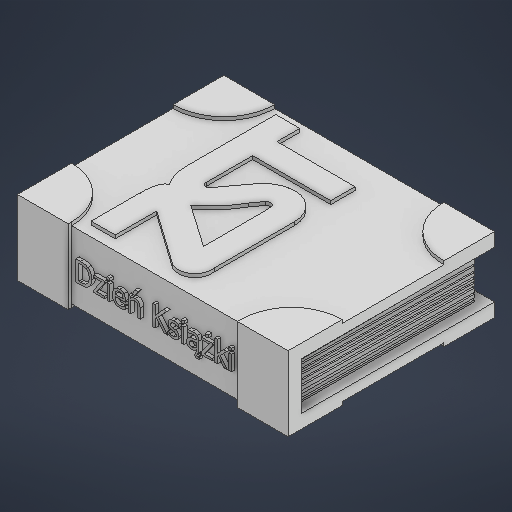
# Autodesk Inventor part: ksiazka
Saved by Autodesk Inventor 2027.1 (Build 311270010, 270A)
## iProperties
Created: 2026-10-06
Part Number: ksiazka
Material: Ogólny
Document SubType Name: Modeling
Designer: Uczeń
Density: 1 g/cm^3
Appearance: Domyślna
Author: Uczeń
Autodesk Inventor part; units mm, degrees
ref_plane "YZ Plane" through (0, 0, 0) normal (1, 0, 0) x (0, 1, 0)
ref_plane "XZ Plane" through (0, 0, 0) normal (0, 1, 0) x (-1, 0, 0)
ref_plane "XY Plane" through (0, 0, 0) normal (0, 0, 1) x (1, 0, 0)
sketch "Szkic3" plane through (0, 0, 0) normal (0, 1, 0) x (-1, 0, 0)
  line L0 (4.3087, 2.9574) -> (-3.6913, 2.9574)
  line L1 (-3.6913, 2.9574) -> (-3.6913, -3.0426)
  line L2 (-3.6913, -3.0426) -> (4.3087, -3.0426)
  line L3 (4.3087, -3.0426) -> (4.3087, 2.9574)
  point P0 (0, 0)
  dimension "d0" = 8
  dimension "d1" = 6
  constraints: 8 end point, 2 parallel, 1 horizontal, 1 perpendicular
  measures "d0" distance of L2.end L1.end
  measures "d1" distance of L1.end L0.end
extrude "Wyciągnięcie proste1" add sketch "Szkic3" along normal blind 2
sketch "Szkic4" plane through (3.6913, 0, 2.9574) normal (1, 0, 0) x (0, 0, -1)
  line L0 (0, 2) -> (6, 2) projected
  line L1 (0, 2) -> (6, 2)
  line L2 (6, 2) -> (6, 0)
  line L3 (6, 0) -> (0, 0)
  line L4 (0, 0) -> (0, 2)
  line L5 (6, 0) -> (6, 0.3)
  line L6 (6, 0.3) -> (0, 0.3)
  line L7 (6, 2) -> (6, 1.7)
  line L8 (6, 1.7) -> (0, 1.7)
  line L9 (0, 1.7) -> (0.3, 1.7)
  line L10 (0.3, 1.7) -> (0.3, 0.3)
  point P0 (2.9574, 0)
  dimension "d4" = 0.3
  dimension "d5" = 0.3
  dimension "d6" = 0.3
  constraints: 20 end point, 6 point on line, 4 perpendicular, 2 parallel, 1 horizontal
  measures "d4" distance of L2.end L5.end
  measures "d5" distance of L1.end L7.end
  measures "d6" distance of L8.end L9.end
extrude "Wyciągnięcie proste2" cut sketch "Szkic4" against normal blind 0.3 contours L2 L6 L10 L8
sketch "Szkic5" plane through (-4.3087, 0, -3.0426) normal (-1, 0, 0) x (0, 0, 1)
  line L0 (6, 2) -> (0, 2) projected
  line L1 (0, 2) -> (0, 1.7)
  line L2 (0, 0) -> (0, 2) projected
  line L3 (0, 1.7) -> (6, 1.7)
  line L4 (6, 0) -> (6, 2) projected
  line L5 (6, 0) -> (0, 0) projected
  line L6 (0, 0) -> (0, 0.3)
  line L7 (0, 0.3) -> (6, 0.3)
  line L8 (5.7, 0.3) -> (5.7, 1.7) projected
  line L9 (5.7, 1.7) -> (5.7, 0.3)
  point P0 (3.0426, 0)
  dimension "d9" = 0.3
  dimension "d10" = 0.3
  constraints: 10 end point, 4 point on line, 2 perpendicular, 1 collinear
  measures "d9" distance of L0.end L1.end
  measures "d10" distance of L2.start L6.end
extrude "Wyciągnięcie proste3" cut sketch "Szkic5" against normal blind 0.3 contours L3 L8 L7 L2
sketch "Szkic6" plane through (3.6913, 0, -3.0426) normal (0, 0, -1) x (-1, 0, 0)
  line L0 (0.3, 1.7) -> (0.3, 0.3) projected
  line L1 (8, 0.3) -> (7.7, 0.3) projected
  line L2 (0.3, 0.3) -> (7.7, 0.3)
  line L3 (7.7, 0.3) -> (7.7, 1.7) projected
  line L4 (7.7, 0.3) -> (7.7, 1.7)
  line L5 (7.7, 1.7) -> (0.3, 1.7)
  line L6 (0.3, 1.7) -> (0.3, 0.3)
  point P0 (3.6913, 0)
  constraints: 8 end point, 3 perpendicular, 1 horizontal
extrude "Wyciągnięcie proste4" cut sketch "Szkic6" against normal blind 0.3
sketch "Szkic7" plane through (0, 2, 0) normal (0, 1, 0) x (1, 0, 0)
  line L0 (-4.3087, 3.0426) -> (3.6913, 3.0426) projected
  line L1 (-4.3087, -2.6574) -> (-4.3087, 3.0426) projected
  circle A0 centre (-4.3087, 3.0426) radius 1.5
  circle A1 centre (3.6913, 3.0426) radius 1.5
  line L2 (3.6913, 3.0426) -> (3.6913, -2.6574) projected
  line L3 (3.6913, 3.0426) -> (3.6913, 1.5426)
  line L4 (3.6913, 3.0426) -> (2.1913, 3.0426)
  line L5 (3.6913, -2.9574) -> (3.6913, 3.0426) projected
  circle A2 centre (3.6913, -2.9574) radius 1.5
  circle A3 centre (-4.3087, -2.9574) radius 1.5
  line L6 (-4.3087, -2.9574) -> (-4.3087, -1.4574)
  line L7 (-4.3087, -2.9574) -> (3.6913, -2.9574) projected
  line L8 (-4.3087, -2.9574) -> (-2.8087, -2.9574)
  line L9 (2.1913, -2.9574) -> (3.6913, -2.9574)
  line L10 (3.6913, -1.4574) -> (3.6913, -2.9574)
  point P0 (0, 0)
  point P1 (-4.3087, 1.5426)
  point P2 (-2.8087, 3.0426)
  point P3 (2.1913, -2.9574)
  point P4 (3.6913, -1.4574)
  dimension "d16" = 3
  dimension "d17" = 3
  dimension "d18" = 3
  dimension "d19" = 3
  constraints: 12 end point, 6 point on circle, 6 point on line, 4 centre point, 2 coincident, 2 collinear
  measures "d16" diameter of A0
  measures "d17" diameter of A1
  measures "d18" diameter of A2
  measures "d19" diameter of A3
extrude "Wyciągnięcie proste5" add sketch "Szkic7" along normal blind 0.1 contours L0 A0 L1 | L0 L2 A1 | A3 L7 L6 L1 | L2 L5 L7 A2 picked at (-3.78, 2.2012) picked at (3.58, 2.0551) picked at (-3.3212, -2.8461) picked at (2.7038, -2.8461)
sketch "Szkic8" plane through (0, 0, 0) normal (0, -1, 0) x (1, 0, 0)
  line L0 (3.6913, -3.0426) -> (-4.3087, -3.0426) projected
  circle A0 centre (-4.3087, -3.0426) radius 1.5
  line L1 (-4.3087, 1.4574) -> (-4.3087, 2.9574) projected
  circle A1 centre (-4.3087, 2.9574) radius 1.5
  line L2 (-4.3087, 2.9574) -> (3.6913, 2.9574) projected
  circle A2 centre (3.6913, 2.9574) radius 1.5
  line L3 (3.6913, 2.9574) -> (3.6913, -3.0426) projected
  circle A3 centre (3.6913, -3.0426) radius 1.5
  line L4 (-4.3087, -3.0426) -> (-4.3087, 2.9574) projected
  line L5 (-4.3087, -1.5426) -> (-4.3087, -3.0426)
  line L6 (-4.3087, -3.0426) -> (-2.8087, -3.0426)
  line L7 (2.1913, -3.0426) -> (3.6913, -3.0426)
  line L8 (3.6913, -1.5426) -> (3.6913, -3.0426)
  line L9 (3.6913, 1.4574) -> (3.6913, 2.9574)
  line L10 (3.6913, 2.9574) -> (2.1913, 2.9574)
  point P0 (0, 0)
  point P1 (-4.3087, -3.0279)
  point P2 (-2.8087, 2.9574)
  dimension "d26" = 3
  dimension "d27" = 3
  dimension "d28" = 3
  dimension "d29" = 3
  constraints: 12 end point, 6 point on circle, 6 point on line, 4 centre point, 3 collinear, 1 coincident, 1 perpendicular
  measures "d26" diameter of A0
  measures "d27" diameter of A1
  measures "d28" diameter of A2
  measures "d29" diameter of A3
extrude "Wyciągnięcie proste6" add sketch "Szkic8" along normal blind 0.1 contours L0 A3 L3 | L0 L4 A0 | A2 L2 L3 | L1 L2 A1 picked at (2.7534, -2.7144) picked at (-3.78, -2.2012) picked at (3.58, 1.9699) picked at (-3.3212, 2.8461)
sketch "Szkic9" plane through (-2.8087, 2, 2.9574) normal (0, 0, 1) x (1, 0, 0)
  line L0 (-1.5, 0.1) -> (0, 0.1) projected
  line L1 (0, -2.1) -> (-1.5, -2.1) projected
  line L2 (0, 0.1) -> (0, -2.1)
  line L3 (5, 0.1) -> (6.5, 0.1) projected
  line L4 (5, -2.1) -> (6.5, -2.1) projected
  line L5 (5, 0.1) -> (5, -2.1)
  line L6 (0.168, -0.6066) -> (4.8954, -0.6066) construction
  line L7 (4.8954, -0.6066) -> (4.8954, -1.5064) construction
  line L8 (4.8954, -1.5064) -> (0.168, -1.5064) construction
  line L9 (0.168, -1.5064) -> (0.168, -0.6066) construction
  line L10 (-1.5, -2.1) -> (-1.5, 0.1) projected
  line L11 (-1.5, -2.1) -> (-1.5, 0.1)
  line L12 (6.5, 0.1) -> (6.5, -2.1)
  spline S0 degree 2 poles (0.7019, -0.9825) (0.7019, -1.0646) (0.6353, -1.1969) (0.5794, -1.2339) knots 0 0 0 1 2 2 2
  spline S1 degree 2 poles (0.5794, -1.2339) (0.5337, -1.2625) (0.4398, -1.282) (0.3669, -1.282) knots 0 0 0 1 2 2 2
  line L13 (0.3669, -1.282) -> (0.2288, -1.282)
  line L14 (0.2288, -1.282) -> (0.2288, -0.682)
  line L15 (0.2288, -0.682) -> (0.3654, -0.682)
  spline S2 degree 2 poles (0.3654, -0.682) (0.45, -0.682) (0.5463, -0.7073) (0.5803, -0.7296) knots 0 0 0 1 2 2 2
  spline S3 degree 2 poles (0.5803, -0.7296) (0.6382, -0.7681) (0.7019, -0.895) (0.7019, -0.9825) knots 0 0 0 1 2 2 2
  spline S4 degree 2 poles (0.6188, -0.9815) (0.6188, -0.9125) (0.5731, -0.8147) (0.5278, -0.787) knots 0 0 0 1 2 2 2
  spline S5 degree 2 poles (0.5278, -0.787) (0.4957, -0.7681) (0.4233, -0.751) (0.3693, -0.751) knots 0 0 0 1 2 2 2
  line L16 (0.3693, -0.751) -> (0.3085, -0.751)
  line L17 (0.3085, -0.751) -> (0.3085, -1.2129)
  line L18 (0.3085, -1.2129) -> (0.3693, -1.2129)
  spline S6 degree 2 poles (0.3693, -1.2129) (0.4223, -1.2129) (0.5026, -1.1959) (0.5351, -1.1731) knots 0 0 0 1 2 2 2
  spline S7 degree 2 poles (0.5351, -1.1731) (0.5769, -1.1449) (0.6188, -1.0515) (0.6188, -0.9815) knots 0 0 0 1 2 2 2
  line L19 (1.0782, -1.282) -> (0.7476, -1.282)
  line L20 (0.7476, -1.282) -> (0.7476, -1.2256)
  line L21 (0.7476, -1.2256) -> (0.9829, -0.894)
  line L22 (0.9829, -0.894) -> (0.7573, -0.894)
  line L23 (0.7573, -0.894) -> (0.7573, -0.8317)
  line L24 (0.7573, -0.8317) -> (1.0739, -0.8317)
  line L25 (1.0739, -0.8317) -> (1.0739, -0.8857)
  line L26 (1.0739, -0.8857) -> (0.8376, -1.2183)
  line L27 (0.8376, -1.2183) -> (1.0782, -1.2183)
  line L28 (1.0782, -1.2183) -> (1.0782, -1.282)
  line L29 (1.2265, -1.282) -> (1.1507, -1.282)
  line L30 (1.1507, -1.282) -> (1.1507, -0.8317)
  line L31 (1.1507, -0.8317) -> (1.2265, -0.8317)
  line L32 (1.2265, -0.8317) -> (1.2265, -1.282)
  line L33 (1.2319, -0.7569) -> (1.1458, -0.7569)
  line L34 (1.1458, -0.7569) -> (1.1458, -0.6781)
  line L35 (1.1458, -0.6781) -> (1.2319, -0.6781)
  line L36 (1.2319, -0.6781) -> (1.2319, -0.7569)
  spline S8 degree 2 poles (1.5333, -1.2922) (1.4254, -1.2922) (1.3068, -1.1711) (1.3068, -1.0593) knots 0 0 0 1 2 2 2
  spline S9 degree 2 poles (1.3068, -1.0593) (1.3068, -0.9494) (1.422, -0.8191) (1.5149, -0.8191) knots 0 0 0 1 2 2 2
  spline S10 degree 2 poles (1.5149, -0.8191) (1.5567, -0.8191) (1.6214, -0.8434) (1.6452, -0.8692) knots 0 0 0 1 2 2 2
  spline S11 degree 2 poles (1.6452, -0.8692) (1.6695, -0.895) (1.6953, -0.9693) (1.6953, -1.0233) knots 0 0 0 1 2 2 2
  line L37 (1.6953, -1.0233) -> (1.6953, -1.0646)
  line L38 (1.6953, -1.0646) -> (1.3836, -1.0646)
  spline S12 degree 2 poles (1.3836, -1.0646) (1.3836, -1.1429) (1.4624, -1.2261) (1.5324, -1.2261) knots 0 0 0 1 2 2 2
  spline S13 degree 2 poles (1.5324, -1.2261) (1.5572, -1.2261) (1.6053, -1.2149) (1.6248, -1.2061) knots 0 0 0 1 2 2 2
  spline S14 degree 2 poles (1.6248, -1.2061) (1.6452, -1.1964) (1.6734, -1.1794) (1.6826, -1.1716) knots 0 0 0 1 2 2 2
  line L39 (1.6826, -1.1716) -> (1.687, -1.1716)
  line L40 (1.687, -1.1716) -> (1.687, -1.2543)
  spline S15 degree 2 poles (1.687, -1.2543) (1.6739, -1.2596) (1.634, -1.2752) (1.6184, -1.2796) knots 0 0 0 1 2 2 2
  spline S16 degree 2 poles (1.6184, -1.2796) (1.5966, -1.2859) (1.5606, -1.2922) (1.5333, -1.2922) knots 0 0 0 1 2 2 2
  spline S17 degree 2 poles (1.6214, -1.0068) (1.6204, -0.9762) (1.6077, -0.9314) (1.5956, -0.9163) knots 0 0 0 1 2 2 2
  spline S18 degree 2 poles (1.5956, -0.9163) (1.5825, -0.8993) (1.5411, -0.8813) (1.5105, -0.8813) knots 0 0 0 1 2 2 2
  spline S19 degree 2 poles (1.5105, -0.8813) (1.4803, -0.8813) (1.438, -0.8993) (1.4205, -0.9168) knots 0 0 0 1 2 2 2
  spline S20 degree 2 poles (1.4205, -0.9168) (1.4035, -0.9348) (1.386, -0.9781) (1.3836, -1.0068) knots 0 0 0 1 2 2 2
  line L41 (1.3836, -1.0068) -> (1.6214, -1.0068)
  line L42 (2.1256, -1.282) -> (2.0497, -1.282)
  line L43 (2.0497, -1.282) -> (2.0497, -1.0253)
  spline S21 degree 2 poles (2.0497, -1.0253) (2.0497, -0.9941) (2.0439, -0.9407) (2.0351, -0.9246) knots 0 0 0 1 2 2 2
  spline S22 degree 2 poles (2.0351, -0.9246) (2.0259, -0.9076) (1.9928, -0.8911) (1.9646, -0.8911) knots 0 0 0 1 2 2 2
  spline S23 degree 2 poles (1.9646, -0.8911) (1.9364, -0.8911) (1.8766, -0.9212) (1.8479, -0.9455) knots 0 0 0 1 2 2 2
  line L44 (1.8479, -0.9455) -> (1.8479, -1.282)
  line L45 (1.8479, -1.282) -> (1.7721, -1.282)
  line L46 (1.7721, -1.282) -> (1.7721, -0.8317)
  line L47 (1.7721, -0.8317) -> (1.8479, -0.8317)
  line L48 (1.8479, -0.8317) -> (1.8479, -0.8818)
  spline S24 degree 2 poles (1.8479, -0.8818) (1.882, -0.8512) (1.9476, -0.8191) (1.9846, -0.8191) knots 0 0 0 1 2 2 2
  spline S25 degree 2 poles (1.9846, -0.8191) (2.0507, -0.8191) (2.1256, -0.9066) (2.1256, -0.9898) knots 0 0 0 1 2 2 2
  line L49 (2.1256, -0.9898) -> (2.1256, -1.282)
  line L50 (2.0677, -0.6066) -> (1.9578, -0.7574)
  line L51 (1.9578, -0.7574) -> (1.8975, -0.7574)
  line L52 (1.8975, -0.7574) -> (1.9695, -0.6066)
  line L53 (1.9695, -0.6066) -> (2.0677, -0.6066)
  line L54 (2.9332, -1.282) -> (2.8296, -1.282)
  line L55 (2.8296, -1.282) -> (2.6103, -1.0029)
  line L56 (2.6103, -1.0029) -> (2.5753, -1.0423)
  line L57 (2.5753, -1.0423) -> (2.5753, -1.282)
  line L58 (2.5753, -1.282) -> (2.4956, -1.282)
  line L59 (2.4956, -1.282) -> (2.4956, -0.682)
  line L60 (2.4956, -0.682) -> (2.5753, -0.682)
  line L61 (2.5753, -0.682) -> (2.5753, -0.9577)
  line L62 (2.5753, -0.9577) -> (2.8214, -0.682)
  line L63 (2.8214, -0.682) -> (2.9186, -0.682)
  line L64 (2.9186, -0.682) -> (2.6701, -0.9499)
  line L65 (2.6701, -0.9499) -> (2.9332, -1.282)
  spline S26 degree 2 poles (3.0966, -1.2927) (3.0513, -1.2927) (2.9731, -1.2684) (2.9473, -1.2548) knots 0 0 0 1 2 2 2
  line L66 (2.9473, -1.2548) -> (2.9473, -1.1697)
  line L67 (2.9473, -1.1697) -> (2.9512, -1.1697)
  spline S27 degree 2 poles (2.9512, -1.1697) (2.9609, -1.1775) (2.9872, -1.1959) (3.009, -1.2061) knots 0 0 0 1 2 2 2
  spline S28 degree 2 poles (3.009, -1.2061) (3.028, -1.2154) (3.0747, -1.229) (3.0995, -1.229) knots 0 0 0 1 2 2 2
  spline S29 degree 2 poles (3.0995, -1.229) (3.1175, -1.229) (3.1588, -1.2207) (3.1685, -1.2139) knots 0 0 0 1 2 2 2
  spline S30 degree 2 poles (3.1685, -1.2139) (3.1826, -1.2047) (3.1953, -1.1838) (3.1953, -1.1624) knots 0 0 0 1 2 2 2
  spline S31 degree 2 poles (3.1953, -1.1624) (3.1953, -1.1356) (3.1661, -1.1079) (3.1286, -1.0987) knots 0 0 0 1 2 2 2
  spline S32 degree 2 poles (3.1286, -1.0987) (3.1141, -1.0953) (3.0674, -1.0856) (3.0474, -1.0802) knots 0 0 0 1 2 2 2
  spline S33 degree 2 poles (3.0474, -1.0802) (2.9959, -1.0651) (2.9492, -1.0029) (2.9492, -0.9587) knots 0 0 0 1 2 2 2
  spline S34 degree 2 poles (2.9492, -0.9587) (2.9492, -0.8974) (3.0411, -0.8211) (3.117, -0.8211) knots 0 0 0 1 2 2 2
  spline S35 degree 2 poles (3.117, -0.8211) (3.1544, -0.8211) (3.2303, -0.8395) (3.256, -0.8536) knots 0 0 0 1 2 2 2
  line L68 (3.256, -0.8536) -> (3.256, -0.9348)
  line L69 (3.256, -0.9348) -> (3.2521, -0.9348)
  spline S36 degree 2 poles (3.2521, -0.9348) (3.223, -0.9115) (3.152, -0.8847) (3.1155, -0.8847) knots 0 0 0 1 2 2 2
  spline S37 degree 2 poles (3.1155, -0.8847) (3.0781, -0.8847) (3.0265, -0.9163) (3.0265, -0.948) knots 0 0 0 1 2 2 2
  spline S38 degree 2 poles (3.0265, -0.948) (3.0265, -0.9766) (3.0572, -1.0044) (3.0912, -1.0131) knots 0 0 0 1 2 2 2
  spline S39 degree 2 poles (3.0912, -1.0131) (3.1077, -1.0175) (3.1496, -1.0262) (3.1724, -1.0316) knots 0 0 0 1 2 2 2
  spline S40 degree 2 poles (3.1724, -1.0316) (3.222, -1.0442) (3.2726, -1.1021) (3.2726, -1.1522) knots 0 0 0 1 2 2 2
  spline S41 degree 2 poles (3.2726, -1.1522) (3.2726, -1.1813) (3.2497, -1.2329) (3.2273, -1.2518) knots 0 0 0 1 2 2 2
  spline S42 degree 2 poles (3.2273, -1.2518) (3.2035, -1.2718) (3.1427, -1.2927) (3.0966, -1.2927) knots 0 0 0 1 2 2 2
  line L70 (3.4204, -1.282) -> (3.3445, -1.282)
  line L71 (3.3445, -1.282) -> (3.3445, -0.8317)
  line L72 (3.3445, -0.8317) -> (3.4204, -0.8317)
  line L73 (3.4204, -0.8317) -> (3.4204, -1.282)
  line L74 (3.4257, -0.7569) -> (3.3397, -0.7569)
  line L75 (3.3397, -0.7569) -> (3.3397, -0.6781)
  line L76 (3.3397, -0.6781) -> (3.4257, -0.6781)
  line L77 (3.4257, -0.6781) -> (3.4257, -0.7569)
  spline S43 degree 2 poles (3.7826, -1.2343) (3.7734, -1.2411) (3.7423, -1.2655) (3.7277, -1.2728) knots 0 0 0 1 2 2 2
  spline S44 degree 2 poles (3.7277, -1.2728) (3.7077, -1.2834) (3.6703, -1.2946) (3.6363, -1.2946) knots 0 0 0 1 2 2 2
  spline S45 degree 2 poles (3.6363, -1.2946) (3.6085, -1.2946) (3.5585, -1.2737) (3.5395, -1.2548) knots 0 0 0 1 2 2 2
  spline S46 degree 2 poles (3.5395, -1.2548) (3.5215, -1.2363) (3.4996, -1.1818) (3.4996, -1.1517) knots 0 0 0 1 2 2 2
  spline S47 degree 2 poles (3.4996, -1.1517) (3.4996, -1.105) (3.539, -1.0389) (3.5818, -1.0199) knots 0 0 0 1 2 2 2
  spline S48 degree 2 poles (3.5818, -1.0199) (3.6197, -1.0024) (3.7228, -0.9893) (3.7826, -0.9859) knots 0 0 0 1 2 2 2
  line L78 (3.7826, -0.9859) -> (3.7826, -0.9713)
  spline S49 degree 2 poles (3.7826, -0.9713) (3.7826, -0.945) (3.7666, -0.9125) (3.752, -0.9032) knots 0 0 0 1 2 2 2
  spline S50 degree 2 poles (3.752, -0.9032) (3.7374, -0.894) (3.6956, -0.8881) (3.6732, -0.8881) knots 0 0 0 1 2 2 2
  spline S51 degree 2 poles (3.6732, -0.8881) (3.647, -0.8881) (3.576, -0.9037) (3.5405, -0.9188) knots 0 0 0 1 2 2 2
  line L79 (3.5405, -0.9188) -> (3.5361, -0.9188)
  line L80 (3.5361, -0.9188) -> (3.5361, -0.8415)
  spline S52 degree 2 poles (3.5361, -0.8415) (3.557, -0.8356) (3.6353, -0.8211) (3.6737, -0.8211) knots 0 0 0 1 2 2 2
  spline S53 degree 2 poles (3.6737, -0.8211) (3.7204, -0.8211) (3.7841, -0.8356) (3.8094, -0.8546) knots 0 0 0 1 2 2 2
  spline S54 degree 2 poles (3.8094, -0.8546) (3.8342, -0.8731) (3.8585, -0.9319) (3.8585, -0.9742) knots 0 0 0 1 2 2 2
  line L81 (3.8585, -0.9742) -> (3.8585, -1.282)
  line L82 (3.8585, -1.282) -> (3.7826, -1.282)
  line L83 (3.7826, -1.282) -> (3.7826, -1.2343)
  line L84 (3.7826, -1.1711) -> (3.7826, -1.0462)
  spline S55 degree 2 poles (3.7826, -1.0462) (3.7554, -1.0486) (3.6732, -1.0569) (3.6474, -1.0646) knots 0 0 0 1 2 2 2
  spline S56 degree 2 poles (3.6474, -1.0646) (3.6173, -1.0739) (3.5779, -1.1123) (3.5779, -1.1463) knots 0 0 0 1 2 2 2
  spline S57 degree 2 poles (3.5779, -1.1463) (3.5779, -1.1852) (3.6217, -1.2246) (3.6635, -1.2246) knots 0 0 0 1 2 2 2
  spline S58 degree 2 poles (3.6635, -1.2246) (3.699, -1.2246) (3.7573, -1.194) (3.7826, -1.1711) knots 0 0 0 1 2 2 2
  spline S59 degree 2 poles (3.8487, -1.282) (3.8312, -1.2966) (3.805, -1.3399) (3.805, -1.3588) knots 0 0 0 1 2 2 2
  spline S60 degree 2 poles (3.805, -1.3588) (3.805, -1.3719) (3.8201, -1.3885) (3.8351, -1.3885) knots 0 0 0 1 2 2 2
  spline S61 degree 2 poles (3.8351, -1.3885) (3.8434, -1.3885) (3.8585, -1.3846) (3.8633, -1.3826) knots 0 0 0 1 2 2 2
  line L85 (3.8633, -1.3826) -> (3.8677, -1.3826)
  line L86 (3.8677, -1.3826) -> (3.8677, -1.439)
  spline S62 degree 2 poles (3.8677, -1.439) (3.856, -1.4439) (3.8303, -1.4483) (3.8196, -1.4483) knots 0 0 0 1 2 2 2
  spline S63 degree 2 poles (3.8196, -1.4483) (3.7836, -1.4483) (3.7427, -1.4108) (3.7427, -1.3773) knots 0 0 0 1 2 2 2
  spline S64 degree 2 poles (3.7427, -1.3773) (3.7427, -1.351) (3.7709, -1.299) (3.7889, -1.282) knots 0 0 0 1 2 2 2
  line L87 (3.7889, -1.282) -> (3.8487, -1.282)
  line L88 (4.2606, -1.282) -> (3.9299, -1.282)
  line L89 (3.9299, -1.282) -> (3.9299, -1.2256)
  line L90 (3.9299, -1.2256) -> (4.1653, -0.894)
  line L91 (4.1653, -0.894) -> (3.9397, -0.894)
  line L92 (3.9397, -0.894) -> (3.9397, -0.8317)
  line L93 (3.9397, -0.8317) -> (4.2562, -0.8317)
  line L94 (4.2562, -0.8317) -> (4.2562, -0.8857)
  line L95 (4.2562, -0.8857) -> (4.0199, -1.2183)
  line L96 (4.0199, -1.2183) -> (4.2606, -1.2183)
  line L97 (4.2606, -1.2183) -> (4.2606, -1.282)
  line L98 (4.1346, -0.7564) -> (4.0486, -0.7564)
  line L99 (4.0486, -0.7564) -> (4.0486, -0.6776)
  line L100 (4.0486, -0.6776) -> (4.1346, -0.6776)
  line L101 (4.1346, -0.6776) -> (4.1346, -0.7564)
  line L102 (4.7045, -1.282) -> (4.6048, -1.282)
  line L103 (4.6048, -1.282) -> (4.4376, -1.0646)
  line L104 (4.4376, -1.0646) -> (4.4074, -1.0938)
  line L105 (4.4074, -1.0938) -> (4.4074, -1.282)
  line L106 (4.4074, -1.282) -> (4.3316, -1.282)
  line L107 (4.3316, -1.282) -> (4.3316, -0.6552)
  line L108 (4.3316, -0.6552) -> (4.4074, -0.6552)
  line L109 (4.4074, -0.6552) -> (4.4074, -1.0219)
  line L110 (4.4074, -1.0219) -> (4.5854, -0.8317)
  line L111 (4.5854, -0.8317) -> (4.6797, -0.8317)
  line L112 (4.6797, -0.8317) -> (4.4949, -1.0199)
  line L113 (4.4949, -1.0199) -> (4.7045, -1.282)
  line L114 (4.8197, -1.282) -> (4.7439, -1.282)
  line L115 (4.7439, -1.282) -> (4.7439, -0.8317)
  line L116 (4.7439, -0.8317) -> (4.8197, -0.8317)
  line L117 (4.8197, -0.8317) -> (4.8197, -1.282)
  line L118 (4.8251, -0.7569) -> (4.739, -0.7569)
  line L119 (4.739, -0.7569) -> (4.739, -0.6781)
  line L120 (4.739, -0.6781) -> (4.8251, -0.6781)
  line L121 (4.8251, -0.6781) -> (4.8251, -0.7569)
  point P0 (2.8087, -2)
  constraints: 8 end point, 2 vertical, 1 collinear, 1 perpendicular, 2 other
extrude "Wyciągnięcie proste7" add sketch "Szkic9" along normal blind 0.1
sketch "Szkic10" plane through (0, 2, 0) normal (0, 1, 0) x (1, 0, 0)
  line L0 (-2.5369, -2.6492) -> (-1.8273, -2.6492)
  line L1 (-1.8273, -2.6492) -> (-1.8273, -1.4232)
  line L2 (-0.2303, -1.6373) -> (-0.2303, 0.1352)
  line L3 (-1.8273, -1.4232) -> (-0.2303, -2.5494)
  line L4 (0.481, -2.0362) -> (0.481, 0.3517)
  arc A0 (-0.2303, -2.5494) -> (0.481, -2.0362) centre (-0.0008, -2.1179) ccw
  line L5 (-1.4779, -0.7683) -> (-0.2303, -1.6373)
  arc A1 (-1.4779, -0.7683) -> (-0.6777, 0.1352) centre (-3.1229, 1.4948) ccw
  arc A2 (-0.4511, 0.422) -> (-0.6777, 0.1352) centre (0.8334, -0.8257) ccw
  arc A3 (-0.2487, 0.3742) -> (-0.4511, 0.422) centre (-0.3566, 0.3699) ccw
  arc A4 (-0.2303, 0.1352) -> (-0.2487, 0.3742) centre (-1.2429, 0.1774) ccw
  arc A5 (0.481, 0.3517) -> (-0.4687, 1.1215) centre (-0.3058, 0.3517) ccw
  arc A6 (-0.4687, 1.1215) -> (-1.0286, 0.7827) centre (-0.2631, 0.1495) ccw
  line L6 (-1.0286, 0.7827) -> (-1.6248, -0.0201)
  line L7 (-1.8273, 1.4122) -> (-1.8273, 0.0497)
  arc A7 (-1.8273, 0.0497) -> (-1.6248, -0.0201) centre (-1.7212, 0.0288) ccw
  line L8 (-1.8273, 1.4122) -> (0.481, 1.4122)
  line L9 (0.481, 1.4122) -> (0.481, 2.1298)
  line L10 (0.481, 2.1298) -> (-1.8273, 2.1298)
  line L11 (-1.8273, 2.1298) -> (-1.8273, 2.805)
  line L12 (-1.8273, 2.805) -> (-2.5369, 2.805)
  line L13 (-2.5369, 2.805) -> (-2.5369, 0.1495)
  arc A8 (-2.5369, 0.1495) -> (-2.3243, -0.5581) centre (-1.2532, 0.1495) ccw
  line L14 (-2.5369, -2.6492) -> (-2.5369, -1.2028)
  arc A9 (-2.4826, -0.7511) -> (-2.5369, -1.2028) centre (-0.6308, -1.2028) ccw
  arc A10 (-2.3243, -0.5581) -> (-2.4826, -0.7511) centre (-2.2025, -0.8194) ccw
  point P0 (0, 0)
  dimension "d104" = 1
  constraints: 30 end point, 22 point on circle, 11 centre point, 5 perpendicular, 5 tangent, 4 vertical, 3 horizontal
  measures "d104" distance of L6.start L6.end
extrude "Wyciągnięcie proste8" add sketch "Szkic10" along normal blind 0.1
sketch "Szkic11" plane through (3.3913, 0, 2.9574) normal (1, 0, 0) x (0, 0, -1)
  line L0 (5.7, 1.7) -> (5.7, 0.3) projected
  line L1 (0.3, 1.7) -> (5.7, 1.7) projected
  line L2 (5.7, 1.7) -> (0.3, 1.7)
  line L3 (0.3, 0.3) -> (0.3, 1.7) projected
  line L4 (0.3, 1.7) -> (0.3, 0.3)
  line L5 (5.7, 0.3) -> (0.3, 0.3) projected
  line L6 (0.3, 0.3) -> (5.7, 0.3)
  line L7 (5.7, 0.3) -> (5.7, 1.7)
  line L8 (5.7, 1.616) -> (0.3, 1.616)
  line L9 (0.3, 1.5656) -> (5.7, 1.5263)
  line L10 (5.7, 1.4477) -> (0.3, 1.4241)
  line L11 (0.3, 1.3848) -> (5.7, 1.4084)
  line L12 (0.3, 1.3101) -> (5.7, 1.2708)
  line L13 (5.7, 1.2197) -> (0.3, 1.259)
  line L14 (0.3, 1.1608) -> (5.7, 1.0941)
  line L15 (5.7, 1.0508) -> (0.3, 1.1175)
  line L16 (0.3, 1.0507) -> (5.7, 0.9525)
  line L17 (5.7, 0.8935) -> (0.3, 1)
  line L18 (0.3, 0.8935) -> (5.7, 0.8268)
  line L19 (5.7, 0.7835) -> (0.3, 0.8502)
  line L20 (0.3, 0.7482) -> (5.7, 0.7088)
  line L21 (5.7, 0.6538) -> (0.3, 0.6931)
  line L22 (0.3, 0.5831) -> (5.7, 0.5437)
  line L23 (5.7, 0.4966) -> (0.3, 0.4966)
  line L24 (0.3, 0.4062) -> (5.7, 0.4062)
  line L25 (5.7, 0.3512) -> (0.3, 0.3512)
  point P0 (2.9574, 0)
  point P1 (0.3, 0.4062)
  point P2 (0.3, 0.5831)
  point P3 (0.3, 0.7482)
  point P4 (0.3, 1.1608)
  point P5 (0.3, 1.3101)
  point P6 (0.3, 1.3848)
  point P7 (0.3, 1.4241)
  constraints: 40 end point, 11 equal length, 5 horizontal, 44 other
extrude "Wyciągnięcie proste9" cut sketch "Szkic11" against normal blind 0.1 contours L0 L9 L3 L8 | L0 L11 L3 L10 | L0 L13 L3 L12 | L0 L15 L3 L14 | L0 L17 L3 L16 | L0 L19 L3 L18 | L0 L21 L3 L20 | L0 L23 L3 L22 | L0 L25 L3 L24
sketch "Szkic14" plane through (-4.0087, 0, -3.0426) normal (-1, 0, 0) x (0, 0, 1)
  line L0 (0.3, 1.616) -> (0.3, 1.7) projected
  line L1 (0.3, 1.7) -> (0.3, 0.3)
  line L2 (0.3, 0.3512) -> (5.7, 0.3512) projected
  line L3 (5.7, 1.7) -> (5.7, 0.3) projected
  line L4 (0.3, 0.3) -> (5.7, 0.3)
  line L5 (5.7, 0.3) -> (5.7, 1.7)
  line L6 (5.7, 1.7) -> (0.3, 1.7)
  line L7 (5.7, 1.616) -> (0.3, 1.616) projected
  line L8 (0.3, 1.616) -> (5.7, 1.616)
  line L9 (0.3, 1.5263) -> (5.7, 1.5656) projected
  line L10 (0.3, 1.5263) -> (5.7, 1.5656)
  line L11 (5.7, 1.4241) -> (0.3, 1.4477) projected
  line L12 (0.3, 1.4477) -> (5.7, 1.4241)
  line L13 (0.3, 1.4084) -> (5.7, 1.3848) projected
  line L14 (5.7, 1.4241) -> (5.7, 1.3848)
  line L15 (5.7, 1.3848) -> (0.3, 1.4084)
  line L16 (0.3, 1.2197) -> (5.7, 1.259) projected
  line L17 (0.3, 1.2197) -> (5.7, 1.259)
  line L18 (5.7, 1.3101) -> (0.3, 1.2708) projected
  line L19 (5.7, 1.259) -> (5.7, 1.3101)
  line L20 (5.7, 1.3101) -> (0.3, 1.2708)
  line L21 (5.7, 1.1608) -> (0.3, 1.0941) projected
  line L22 (0.3, 1.2708) -> (0.3, 1.2197)
  line L23 (0.3, 0.4062) -> (0.3, 0.3512) projected
  line L24 (0.3, 0.3512) -> (0.3, 0.4062)
  line L25 (5.7, 0.4062) -> (0.3, 0.4062) projected
  line L26 (0.3, 0.4062) -> (5.7, 0.4062)
  line L27 (5.7, 0.4062) -> (5.7, 0.3512)
  line L28 (0.3, 0.4966) -> (5.7, 0.4966) projected
  line L29 (5.7, 0.4966) -> (0.3, 0.4966)
  line L30 (5.7, 0.5831) -> (0.3, 0.5437) projected
  line L31 (0.3, 0.5437) -> (5.7, 0.5831)
  line L32 (5.7, 0.5831) -> (5.7, 0.4966)
  line L33 (0.3, 0.6538) -> (5.7, 0.6931) projected
  line L34 (5.7, 0.6931) -> (0.3, 0.6538)
  line L35 (5.7, 0.7482) -> (0.3, 0.7088) projected
  line L36 (0.3, 0.6538) -> (0.3, 0.7088)
  line L37 (0.3, 0.7088) -> (5.7, 0.7482)
  line L38 (0.3, 1.0508) -> (5.7, 1.1175) projected
  line L39 (0.3, 1.0508) -> (0.3, 1.0508)
  line L40 (0.3, 0.7835) -> (5.7, 0.8502) projected
  line L41 (0.3, 0.7835) -> (5.7, 0.8502)
  line L42 (5.7, 0.8935) -> (0.3, 0.8268) projected
  line L43 (0.3, 0.8268) -> (5.7, 0.8935)
  line L44 (0.3, 0.8935) -> (5.7, 1) projected
  line L45 (0.3, 0.8935) -> (5.7, 1)
  line L46 (5.7, 1.0507) -> (0.3, 0.9525) projected
  line L47 (0.3, 0.9525) -> (5.7, 1.0507)
  point P0 (3.0426, 0)
  constraints: 52 end point, 10 collinear, 4 horizontal, 4 vertical, 3 parallel, 2 perpendicular, 1 point on line, 7 other
extrude "Wyciągnięcie proste10" cut sketch "Szkic14" against normal blind 0.1 contours L7 L3 L9 L1 | L11 L3 L13 L1 | L18 L3 L16 L1 | L21 L3 L38 L1 | L46 L3 L44 L1 | L42 L3 L40 L1 | L35 L3 L33 L1 | L30 L3 L28 L1 | L25 L3 L2 L1
sketch "Szkic15" plane through (3.6913, 0, -2.7426) normal (0, 0, -1) x (-1, 0, 0)
  line L0 (0.3, 1.7) -> (0.4, 1.7)
  line L1 (0, 1.7) -> (8, 1.7) projected
  line L2 (0.4, 1.7) -> (0.4, 0.3)
  line L3 (7.7, 0.3) -> (0.3, 0.3) projected
  line L4 (7.7, 1.7) -> (7.6, 1.7)
  line L5 (7.6, 1.7) -> (7.6, 0.3)
  line L6 (0.3, 1.616) -> (0.4, 1.616) projected
  line L7 (0.4, 1.616) -> (7.6, 1.616)
  line L8 (7.6, 1.616) -> (7.6, 1.5263)
  line L9 (7.6, 1.5263) -> (0.4, 1.5263)
  line L10 (0.4, 1.5263) -> (0.4, 1.616)
  line L11 (0.4, 1.4505) -> (7.6, 1.4505)
  line L12 (7.6, 1.4505) -> (7.6, 1.4084)
  line L13 (7.6, 1.4084) -> (0.4, 1.4084)
  line L14 (0.4, 1.4084) -> (0.4, 1.4505)
  line L15 (0.4, 1.2197) -> (0.3, 1.2197) projected
  line L16 (0.4, 1.2197) -> (7.6, 1.2197)
  line L17 (7.6, 1.2197) -> (7.6, 1.2708)
  line L18 (7.6, 1.2708) -> (0.4, 1.2708)
  line L19 (0.4, 1.2708) -> (0.4, 1.2197)
  line L20 (0.3, 1.0941) -> (0.4, 1.0941) projected
  line L21 (0.4, 1.0941) -> (7.6, 1.0941)
  line L22 (7.6, 1.0941) -> (7.6, 1.0507)
  line L23 (7.6, 1.0507) -> (0.4, 1.0507)
  line L24 (0.4, 1.0507) -> (0.4, 1.0941)
  line L25 (0.3, 0.9525) -> (0.4, 0.9525) projected
  line L26 (0.4, 0.9525) -> (7.6, 0.9525)
  line L27 (7.6, 0.9525) -> (7.6, 0.8935)
  line L28 (7.6, 0.8935) -> (0.4, 0.8935)
  line L29 (0.4, 0.8935) -> (0.4, 0.9525)
  line L30 (0.3, 0.8268) -> (0.4, 0.8268) projected
  line L31 (0.4, 0.8268) -> (7.6, 0.8268)
  line L32 (7.6, 0.8268) -> (7.6, 0.7835)
  line L33 (7.6, 0.7835) -> (0.4, 0.7835)
  line L34 (0.4, 0.7835) -> (0.4, 0.8268)
  line L35 (0.3, 0.7088) -> (0.4, 0.7088) projected
  line L36 (0.4, 0.7088) -> (7.6, 0.7088)
  line L37 (7.6, 0.7088) -> (7.6, 0.6538)
  line L38 (7.6, 0.6538) -> (0.4, 0.6538)
  line L39 (0.4, 0.6538) -> (0.4, 0.7088)
  line L40 (0.3, 0.5437) -> (0.4, 0.5437) projected
  line L41 (0.4, 0.5437) -> (7.6, 0.5437)
  line L42 (7.6, 0.5437) -> (7.6, 0.4966)
  line L43 (7.6, 0.4966) -> (0.4, 0.4966)
  line L44 (0.4, 0.4966) -> (0.4, 0.5437)
  line L45 (0.3, 0.4062) -> (0.4, 0.4062) projected
  line L46 (0.4, 0.4062) -> (7.6, 0.4062)
  line L47 (7.6, 0.4062) -> (7.6, 0.3512)
  line L48 (7.6, 0.3512) -> (0.4, 0.3512)
  line L49 (0.4, 0.3512) -> (0.4, 0.4062)
  point P0 (3.6913, 0)
  dimension "d111" = 0.1
  dimension "d112" = 0.1
  dimension "d113" = 7.2
  dimension "d114" = 7.2
  dimension "d115" = 7.2
  dimension "d116" = 7.2
  dimension "d117" = 7.2
  dimension "d118" = 7.2
  dimension "d119" = 7.2
  dimension "d120" = 7.2
  dimension "d121" = 7.2
  constraints: 76 end point, 18 parallel, 10 horizontal, 9 perpendicular, 5 point on line, 7 other
  measures "d111" distance of L0.start L0.end
  measures "d112" distance of L4.start L4.end
  measures "d113" distance of L8.end L9.end
  measures "d114" distance of L12.end L13.end
  measures "d115" distance of L18.end L17.end
  measures "d116" distance of L22.end L23.end
  measures "d117" distance of L27.end L28.end
  measures "d118" distance of L32.end L33.end
  measures "d119" distance of L37.end L38.end
  measures "d120" distance of L42.end L43.end
  measures "d121" distance of L47.end L48.end
extrude "Wyciągnięcie proste11" cut sketch "Szkic15" against normal blind 0.1 contours L7 L5 L9 L2 | L11 L5 L13 L2 | L18 L5 L16 L2 | L21 L5 L23 L2 | L26 L5 L28 L2 | L31 L5 L33 L2 | L36 L5 L38 L2 | L41 L5 L43 L2 | L46 L5 L48 L2
